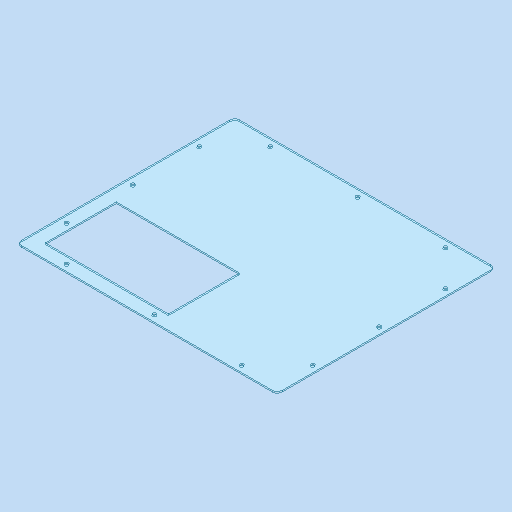
# Autodesk Inventor part: MM0937AN200_G04_110
Saved by Autodesk Inventor 2023.3 (Build 273359000, 359)
## iProperties
Part Number: MM0937AN200_G04_110
Material: Kst - PC (Eslon, klar)
Description: =<RBPARTNOTITLE2>
Document SubType Name: Modeling
Designer: Benutzer
Mass: 768.428 g
Surface Area: 4361.65 cm^2
Volume: 640.357 cm^3
Density: 1.2 g/cm^3
Appearance: Klar AnP
Vendor: Koenig
RBDOCUMENTTYPE: DRF
RBDOCUMENTVERSION: 00
RBDRAWINGMAINSCALE: 1:1
RBDRAWINGMISSINGSPEC: --
RBDRAWINGVOLUME: --
RBGBEDGESIN1: +0,5
RBGBEDGESIN2: +0,2
RBGBEDGESOUT1: -0,3
RBGBEDGESOUT2: -0,1
RBMATERIAL: =<Material>
RBMATMEETS: --
RBMATNO: =<Part Number>
RBPARTMADEOF: 3 x 460 x 550 (FM)
RBPARTNO: SIEHE MNR
RBPARTNOTITLE1: manufactured part
RBPARTNOTITLE2: Anfertigungsteil
RBPARTSAFETYINDICATOR: --
RBSURFACE: --
RBSURFACE2: --
RBZEDGESNORM: ISO13715:2002-06
RBZGENDIMCLASS: m
RBZGENDIMNORM: ISO 2768-1:1989-11
RBZGENGEOCLASS: H
RBZGENGEONORM: ISO 2768-2:1989-11
RBZSURFACENORM: ISO13D2:2002-02
RBZTOLERANCENORM: ISO 14405-1:2010-12
AnP_Material: =<Material>
AnP_TemplVers: 20190222
AnP_Kategorie: 1
MaxAbmaße: 3 x 460 x 550 (FM)
Author: Benutzer
Keywords: =<RBPARTMADEOF>
Comments: =<RBSURFACE2>
Revision Number: 01
Autodesk Inventor part; units mm, degrees
ref_plane "XZ Plane" through (0, 0, 0) normal (0, 1, 0) x (-1, 0, 0)
ref_plane "XY Plane" through (0, 0, 0) normal (0, 0, 1) x (1, 0, 0)
sketch "Skizze1" plane through (0, 0, 0) normal (0, 0, 1) x (1, 0, 0)
  line L0 (0, 0) -> (550, 0)
  line L1 (550, 0) -> (550, 460)
  line L2 (550, 460) -> (0, 460)
  line L3 (0, 460) -> (0, 0)
  dimension "d0" = 550
  dimension "d1" = 460
  constraints: 8 end point, 2 parallel, 1 horizontal, 1 perpendicular
  measures "d0" distance of L2.end L1.end
  measures "d1" distance of L1.end L0.end
extrude "Extrusion1" add sketch "Skizze1" along normal blind 3
fillet "Rundung1" radius 10 4 edges at (550, 0, 1.5) (0, 0, 1.5) (0, 460, 1.5) (550, 460, 1.5)
sketch "Skizze2" plane through (0, 0, 3) normal (0, 0, 1) x (1, 0, 0)
  line L0 (540, 460) -> (10, 460) projected
  line L1 (0, 450) -> (0, 10) projected
  line L2 (550, 10) -> (550, 450) projected
  line L3 (10, 0) -> (540, 0) projected
  point P0 (0, 0)
  point P1 (90, 445)
  point P2 (275, 445)
  point P3 (460, 445)
  point P4 (535, 370)
  point P5 (535, 230)
  point P6 (535, 90)
  point P7 (460, 15)
  point P8 (275, 15)
  point P9 (90, 15)
  point P10 (15, 90)
  point P11 (15, 230)
  point P12 (15, 370)
  dimension "d5" = 15
  dimension "d6" = 15
  dimension "d7" = 15
  dimension "d8" = 15
  dimension "d9" = 185
  dimension "d10" = 185
  dimension "d12" = 550
  dimension "d13" = 90
  dimension "d16" = 140
  dimension "d17" = 460
  dimension "d18" = 90
  dimension "d35" = 140
  constraints: 7 horizontal alignment, 7 vertical alignment
  measures "d5" distance from line of point (90, 445) L0
  measures "d6" distance from line of point (15, 370) L1
  measures "d7" distance from line of point (535, 370) L2
  measures "d8" distance from line of L3 point (90, 15)
  measures "d9" distance of point (275, 15) point (90, 15)
  measures "d10" distance of point (460, 15) point (275, 15)
  measures "d12" distance between parallel lines of L2 L1
  measures "d13" distance from line of point (90, 15) L1
  measures "d16" distance of point (15, 370) point (15, 230)
  measures "d17" distance between parallel lines of L3 L0
  measures "d18" distance from line of point (15, 370) L0
  measures "d35" distance of point (15, 90) point (15, 230)
hole "Bohrung1" at (90, 445, 3) at (275, 445, 3) at (460, 445, 3) at (535, 370, 3) at (535, 230, 3) at (535, 90, 3) at (460, 15, 3) at (275, 15, 3) at (90, 15, 3) at (15, 90, 3) at (15, 230, 3) at (15, 370, 3) direction (0, 0, -1) diameter 7 depth 8 tip angle 118
ref_plane "Arbeitsebene1" through (272.5, 0, 0) normal (1, 0, 0) x (0, 1, 0)
sketch "Skizze4" plane through (0, 0, 3) normal (0, 0, 1) x (1, 0, 0)
  line L0 (30, 30) -> (290, 30)
  line L1 (290, 30) -> (290, 180)
  line L2 (290, 180) -> (30, 180)
  line L3 (30, 180) -> (30, 30)
  line L4 (0, 450) -> (0, 10) projected
  line L5 (10, 0) -> (540, 0) projected
  point P0 (0, 0)
  dimension "d39" = 30
  dimension "d40" = 260
  dimension "d41" = 30
  dimension "d42" = 150
  constraints: 8 end point, 2 parallel, 1 horizontal, 1 perpendicular
  measures "d39" distance between parallel lines of L4 L3
  measures "d40" distance of L0.start L0.end
  measures "d41" distance between parallel lines of L0 L5
  measures "d42" distance of L2.end L0.start
extrude "Extrusion2" cut sketch "Skizze4" against normal through all
